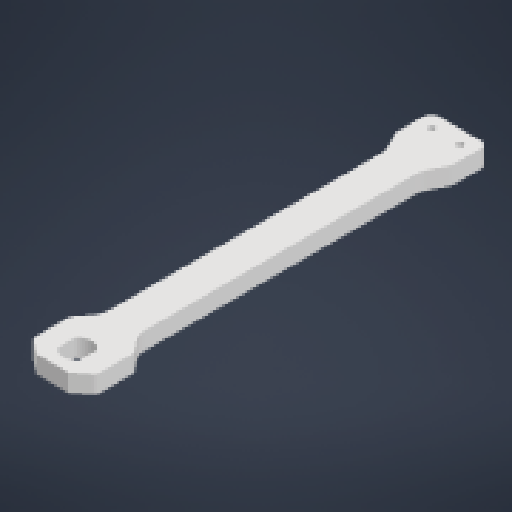
# Autodesk Inventor part: thanh lk
Saved by Autodesk Inventor 2027 (Build 310192060, 192F)
## iProperties
Created: 2026-08-19
Part Number: thanh lk
Material: Generic
Document SubType Name: Modeling
Designer: thita
Density: 1 g/cm^3
Appearance: Default
Author: thita
Autodesk Inventor part; units mm, degrees
ref_plane "YZ Plane" through (0, 0, 0) normal (1, 0, 0) x (0, 1, 0)
ref_plane "XZ Plane" through (0, 0, 0) normal (0, 1, 0) x (-1, 0, 0)
ref_plane "XY Plane" through (0, 0, 0) normal (0, 0, 1) x (1, 0, 0)
sketch "Sketch1" plane through (0, 0, 0) normal (0, 1, 0) x (-1, 0, 0)
  line L0 (3, -2.6458) -> (3, 2.6458)
  arc A0 (3, 2.6458) -> (-3, 2.6458) centre (0, 0) ccw
  arc A1 (-3, -2.6458) -> (3, -2.6458) centre (0, 0) ccw
  line L1 (-3, 2.6458) -> (-3, -2.6458)
  line L2 (-9, -6.2984) -> (-9, 2.5218)
  line L3 (-9, 7) -> (9, -7) construction
  line L4 (9, 7) -> (-9, -7) construction
  line L5 (0, 0) -> (0, -104)
  line L6 (-4, -104) -> (4, -104)
  circle A2 centre (4, -104) radius 1
  circle A3 centre (-4, -104) radius 1
  line L7 (5, -14.1047) -> (5, -90.5836)
  line L8 (-5, -14.1047) -> (-5, -90.5836)
  line L9 (-6, -108) -> (6, -108)
  line L10 (8, -108) -> (-8, -108)
  line L11 (-8, -106) -> (-8, -98.4721)
  line L12 (8, -98.4721) -> (8, -106)
  arc A4 (6, -108) -> (8, -106) centre (6, -106) ccw
  arc A5 (-8, -106) -> (-6, -108) centre (-6, -106) ccw
  line L13 (7.7889, -97.5777) -> (5.6334, -93.2669)
  line L14 (-7.7889, -97.5777) -> (-5.6334, -93.2669)
  arc A6 (5, -90.5836) -> (5.6334, -93.2669) centre (11, -90.5836) ccw
  arc A7 (-5.6334, -93.2669) -> (-5, -90.5836) centre (-11, -90.5836) ccw
  arc A8 (8, -98.4721) -> (7.7889, -97.5777) centre (6, -98.4721) ccw
  arc A9 (-7.7889, -97.5777) -> (-8, -98.4721) centre (-6, -98.4721) ccw
  line L15 (8.5617, -7.5478) -> (6.3148, -10.3565)
  line L16 (-8.5617, -7.5478) -> (-6.3148, -10.3565)
  arc A10 (6.3148, -10.3565) -> (5, -14.1047) centre (11, -14.1047) ccw
  arc A11 (-5, -14.1047) -> (-6.3148, -10.3565) centre (-11, -14.1047) ccw
  arc A12 (8.5617, -7.5478) -> (9, -6.2984) centre (7, -6.2984) ccw
  arc A13 (-9, -6.2984) -> (-8.5617, -7.5478) centre (-7, -6.2984) ccw
  line L17 (-8.2279, 4.1005) -> (-4.5, 7)
  arc A14 (-8.2279, 4.1005) -> (-9, 2.5218) centre (-7, 2.5218) ccw
  line L18 (0, 7) -> (-4.5, 7)
  line L19 (8.2279, 4.1005) -> (4.5, 7)
  arc A15 (9, 2.5218) -> (8.2279, 4.1005) centre (7, 2.5218) ccw
  line L20 (0, 7) -> (4.5, 7)
  line L21 (9, 2.5218) -> (9, -6.2984)
  point P0 (0, 0)
  point P1 (-8, -98)
  point P2 (-5, -92)
  point P3 (-9, 3.5)
  point P4 (9, 3.5)
  dimension "d0" = 18
  dimension "d1" = 14
  dimension "d2" = 104
  dimension "d3" = 8
  dimension "d4" = 2
  dimension "d5" = 2
  dimension "d6" = 5
  dimension "d7" = 5
  dimension "d10" = 10
  dimension "d11" = 2
  dimension "d12" = 2
  dimension "d14" = 6
  dimension "d15" = 2
  dimension "d18" = 6
  dimension "d19" = 2
  dimension "d20" = 2
  constraints: 44 end point, 28 point on circle, 21 tangent, 16 centre point, 12 point on line, 5 symmetric about line, 4 equal radius, 4 parallel, 3 midpoint, 2 coincident, 2 horizontal, 1 perpendicular, 1 vertical, 1 other
  measures "d0" distance of L3.start L4.start
  measures "d1" distance of L4.start L3.end
  measures "d2" distance of L5.start L5.end
  measures "d3" distance of L6.start L6.end
  measures "d4" diameter of A2
  measures "d5" diameter of A3
  measures "d6" distance between parallel lines of L5 L7
  measures "d7" distance between parallel lines of L5 L8
  measures "d10" distance of L10.end point (-8, -98)
  measures "d11" radius of A4
  measures "d12" radius of A5
  measures "d14" radius of A6
  measures "d15" radius of A8
  measures "d18" radius of A10
  measures "d19" radius of A12
  measures "d20" radius of A14
extrude "Extrusion1" add sketch "Sketch1" along normal blind 3
sketch "Sketch2" plane through (5, 0, -14.1047) normal (1, 0, 0) x (0, 0, -1)
  line L0 (0, 0) -> (0, 3) projected
  line L1 (0, 0.25) -> (0, 2.75)
  line L2 (76.4789, 0) -> (76.4789, 3) projected
  line L3 (75.2289, 1.5) -> (77.7289, 1.5)
  line L4 (0, 2.75) -> (76.4789, 2.75)
  line L5 (76.4789, 2.75) -> (76.4789, 3)
  line L6 (76.4789, 3) -> (0, 3)
  line L7 (0, 3) -> (0, 2.75)
  line L8 (0, 0) -> (76.4789, 0) projected
  line L9 (0, 0.25) -> (76.4789, 0.25)
  line L10 (76.4789, 0.25) -> (76.4789, 0)
  line L11 (76.4789, 0) -> (0, 0)
  line L12 (0, 0) -> (0, 0.25)
  point P0 (-14.1047, 0)
  point P1 (0, 1.5)
  point P2 (76.4789, 1.5)
  point P3 (0, 0.25)
  dimension "d23" = 2.5
  dimension "d24" = 2.5
  constraints: 20 end point, 4 midpoint, 4 parallel, 3 horizontal, 2 perpendicular, 1 point on line
  measures "d23" distance of L1.start L1.end
  measures "d24" distance of L3.start L3.end
extrude "Extrusion2" [suppressed]
fillet "Fillet1" [suppressed]
fillet "Fillet2" [suppressed]
sketch "Sketch3" plane through (5, 3.75, -15.5414) normal (0, 1, 0) x (1, 0, 0)
  line L0 (0, 0) -> (-10, 0) projected
  line L1 (-5, 0) -> (-5, 73.6055)
  line L2 (-10, 73.6055) -> (0, 73.6055) projected
  line L3 (-10, 0) -> (-10, 73.6055) projected
  line L4 (-8.75, 1.8028) -> (-8.75, 71.8028)
  line L5 (-8.75, 71.8028) -> (-6.25, 71.8028)
  line L6 (-6.25, 71.8028) -> (-6.25, 1.8028)
  line L7 (-6.25, 1.8028) -> (-8.75, 1.8028)
  line L8 (-8.75, 1.8028) -> (-6.25, 71.8028) construction
  line L9 (-8.75, 71.8028) -> (-6.25, 1.8028) construction
  line L10 (-3.75, 71.8028) -> (-3.75, 1.8028)
  line L11 (-3.75, 1.8028) -> (-1.25, 1.8028)
  line L12 (-1.25, 1.8028) -> (-1.25, 71.8028)
  line L13 (-1.25, 71.8028) -> (-3.75, 71.8028)
  line L14 (-3.75, 71.8028) -> (-1.25, 1.8028) construction
  line L15 (-3.75, 1.8028) -> (-1.25, 71.8028) construction
  point P0 (-5, -15.5414)
  point P1 (-7.5, 36.8028)
  dimension "d29" = 70
  dimension "d30" = 2.5
  dimension "d32" = 70
  dimension "d33" = 2.5
  constraints: 26 end point, 4 midpoint, 4 parallel, 2 perpendicular, 1 vertical
  measures "d29" distance of L4.start L4.end
  measures "d30" distance of L4.end L5.end
  measures "d32" distance of L10.start L10.end
  measures "d33" distance of L11.end L10.end
extrude "Extrusion3" [suppressed]
chamfer "Chamfer1" [suppressed]
body "Solid1"
